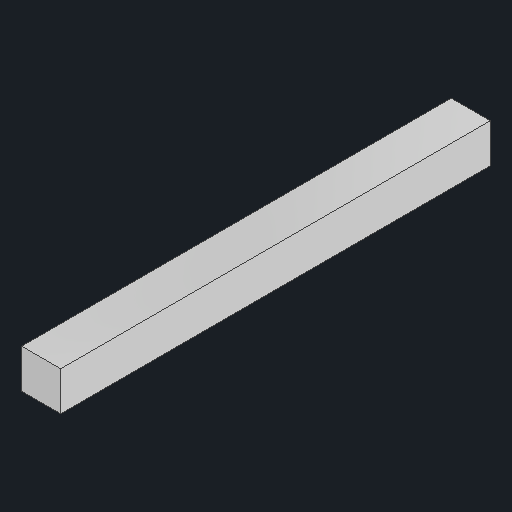
# Autodesk Inventor part: ra_worm_carrier_shim
Saved by Autodesk Inventor 2027.1 (Build 311270010, 270A)
## iProperties
Created: 2026-11-03
Part Number: ra_worm_carrier_shim
Material: Generic
Description: Bare-metal strip beside the worm carrier (seen in photo 19)
Document SubType Name: Modeling
Designer: Claude (from photos)
Density: 1 g/cm^3
Appearance: Aluminum - Polished
Author: alexg
Autodesk Inventor part; units mm, degrees
ref_plane "YZ Plane" through (0, 0, 0) normal (1, 0, 0) x (0, 1, 0)
ref_plane "XY Plane" through (0, 0, 0) normal (0, 0, 1) x (1, 0, 0)
ref_plane "Work Plane1" through (0, -52, 0) normal (0, 1, 0) x (-1, 0, 0)
sketch "Carrier shim sketch" plane through (0, -52, 0) normal (0, 1, 0) x (-1, 0, 0)
  line L0 (-29.4, -22) -> (-33.4, -22)
  line L1 (-33.4, -22) -> (-33.4, 22)
  line L2 (-33.4, 22) -> (-29.4, 22)
  line L3 (-29.4, 22) -> (-29.4, -22)
  constraints: 8 end point, 2 parallel, 1 horizontal, 1 perpendicular
extrude "Carrier shim" add sketch "Carrier shim sketch" along normal blind 4
body "Solid1"
